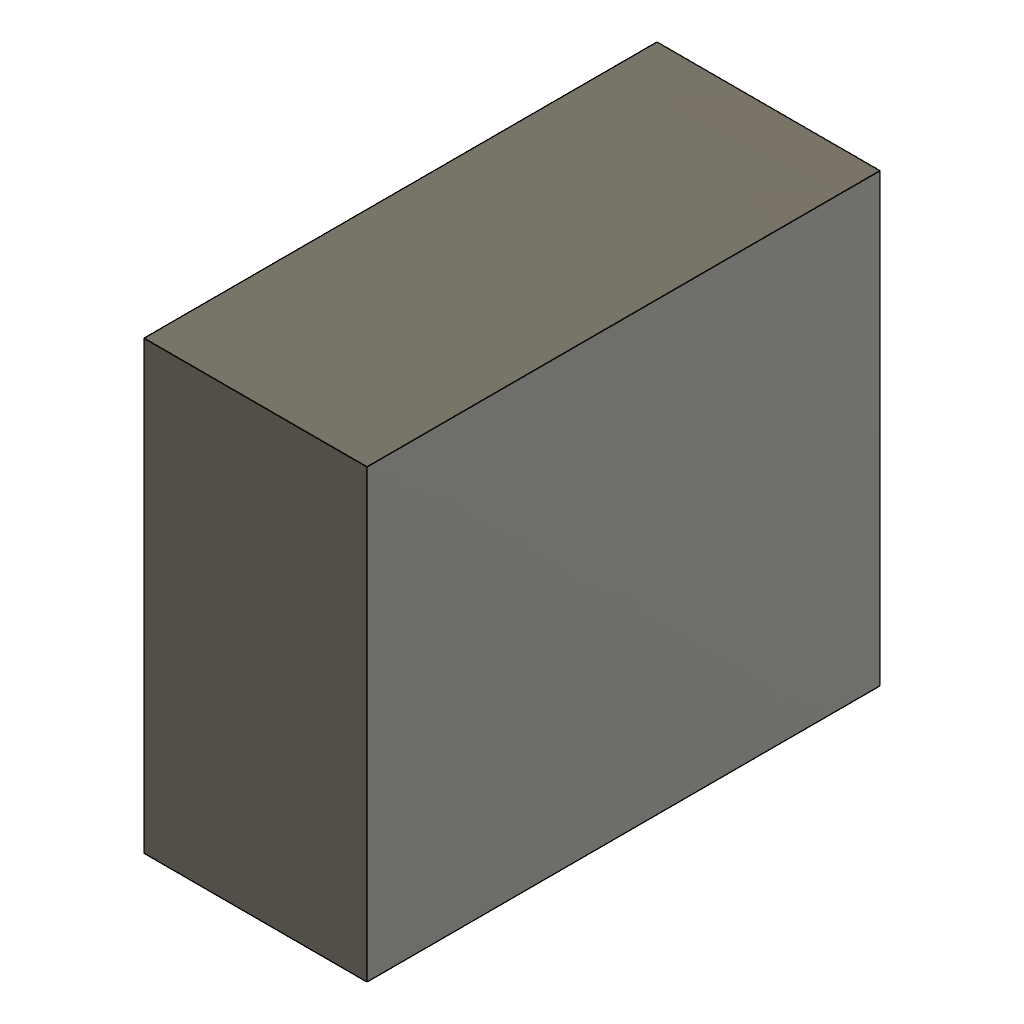
variation (Autodesk Fusion 360 design; units mm, degrees)
part number: 2026-11-22-19-25-15-995
Autodesk Fusion 360 part; units mm, degrees
sketch "Sketch1" plane through (0, 0, 0) normal (1, 0, 0) x (0, 0, -1)
  line L0 (0, 0) -> (23, 0)
  line L1 (23, 0) -> (23, 20)
  line L2 (23, 20) -> (0, 20)
  line L3 (0, 20) -> (0, 0)
extrude "ControlledBoss" add sketch "Sketch1" against normal blind 10
